Autodesk Fusion 360 part; units mm, degrees
(part 4 of 5)
sketch "cheekR_pa10" plane through (89.6, 0, 0) normal (1, 0, 0) x (0, 0, -1)
  line L0 (18.5, 27) -> (14.8, 27)
  line L1 (14.8, 27) -> (11.1, 27)
  line L2 (11.1, 27) -> (7.4, 27)
  line L3 (7.4, 27) -> (3.7, 27)
  line L4 (3.7, 27) -> (0, 27)
  line L5 (0, 27) -> (-3.7, 27)
  line L6 (-3.7, 27) -> (-7.4, 27)
  line L7 (-7.4, 27) -> (-11.1, 27)
  line L8 (-11.1, 27) -> (-14.8, 27)
  line L9 (-14.8, 27) -> (-18.5, 27)
  line L10 (-18.5, 27) -> (-18.5, 25)
  line L11 (-18.5, 25) -> (-14.8, 25)
  line L12 (-14.8, 25) -> (-11.1, 25)
  line L13 (-11.1, 25) -> (-7.4, 25)
  line L14 (-7.4, 25) -> (-3.7, 25)
  line L15 (-3.7, 25) -> (0, 25)
  line L16 (0, 25) -> (3.7, 25)
  line L17 (3.7, 25) -> (7.4, 25)
  line L18 (7.4, 25) -> (11.1, 25)
  line L19 (11.1, 25) -> (14.8, 25)
  line L20 (14.8, 25) -> (18.5, 25)
  line L21 (18.5, 25) -> (18.5, 27)
ref_plane "WorkPlane94" through (120.4, 0, 0) normal (1, 0, 0) x (0, 1, 0)
sketch "cheekR_pb10" plane through (120.4, 0, 0) normal (1, 0, 0) x (0, 0, -1)
  line L0 (18.5, 27) -> (14.8, 27)
  line L1 (14.8, 27) -> (11.1, 27)
  line L2 (11.1, 27) -> (7.4, 27)
  line L3 (7.4, 27) -> (3.7, 27)
  line L4 (3.7, 27) -> (0, 27)
  line L5 (0, 27) -> (-3.7, 27)
  line L6 (-3.7, 27) -> (-7.4, 27)
  line L7 (-7.4, 27) -> (-11.1, 27)
  line L8 (-11.1, 27) -> (-14.8, 27)
  line L9 (-14.8, 27) -> (-18.5, 27)
  line L10 (-18.5, 27) -> (-18.5, 25)
  line L11 (-18.5, 25) -> (-14.8, 25)
  line L12 (-14.8, 25) -> (-11.1, 25)
  line L13 (-11.1, 25) -> (-7.4, 25)
  line L14 (-7.4, 25) -> (-3.7, 25)
  line L15 (-3.7, 25) -> (0, 25)
  line L16 (0, 25) -> (3.7, 25)
  line L17 (3.7, 25) -> (7.4, 25)
  line L18 (7.4, 25) -> (11.1, 25)
  line L19 (11.1, 25) -> (14.8, 25)
  line L20 (14.8, 25) -> (18.5, 25)
  line L21 (18.5, 25) -> (18.5, 27)
loft "Loft47" add profiles "cheekR_pa10", "cheekR_pb10" section 1 section 2 separate body makes body 47
ref_plane "WorkPlane95" through (119.6, 0, 0) normal (1, 0, 0) x (0, 1, 0)
sketch "cheekR_pa11" plane through (119.6, 0, 0) normal (1, 0, 0) x (0, 0, -1)
  line L0 (18.5, 27) -> (14.8, 27)
  line L1 (14.8, 27) -> (11.1, 27)
  line L2 (11.1, 27) -> (7.4, 27)
  line L3 (7.4, 27) -> (3.7, 27)
  line L4 (3.7, 27) -> (0, 27)
  line L5 (0, 27) -> (-3.7, 27)
  line L6 (-3.7, 27) -> (-7.4, 27)
  line L7 (-7.4, 27) -> (-11.1, 27)
  line L8 (-11.1, 27) -> (-14.8, 27)
  line L9 (-14.8, 27) -> (-18.5, 27)
  line L10 (-18.5, 27) -> (-18.5, 25)
  line L11 (-18.5, 25) -> (-14.8, 25)
  line L12 (-14.8, 25) -> (-11.1, 25)
  line L13 (-11.1, 25) -> (-7.4, 25)
  line L14 (-7.4, 25) -> (-3.7, 25)
  line L15 (-3.7, 25) -> (0, 25)
  line L16 (0, 25) -> (3.7, 25)
  line L17 (3.7, 25) -> (7.4, 25)
  line L18 (7.4, 25) -> (11.1, 25)
  line L19 (11.1, 25) -> (14.8, 25)
  line L20 (14.8, 25) -> (18.5, 25)
  line L21 (18.5, 25) -> (18.5, 27)
ref_plane "WorkPlane96" through (124.6857, 0, 0) normal (1, 0, 0) x (0, 1, 0)
sketch "cheekR_pb11" plane through (124.6857, 0, 0) normal (1, 0, 0) x (0, 0, -1)
  line L0 (16.3003, 24.3221) -> (13.0402, 24.3221)
  line L1 (13.0402, 24.3221) -> (9.7802, 24.3221)
  line L2 (9.7802, 24.3221) -> (6.5201, 24.3221)
  line L3 (6.5201, 24.3221) -> (3.2601, 24.3221)
  line L4 (3.2601, 24.3221) -> (0, 24.3221)
  line L5 (0, 24.3221) -> (-3.2601, 24.3221)
  line L6 (-3.2601, 24.3221) -> (-6.5201, 24.3221)
  line L7 (-6.5201, 24.3221) -> (-9.7802, 24.3221)
  line L8 (-9.7802, 24.3221) -> (-13.0402, 24.3221)
  line L9 (-13.0402, 24.3221) -> (-16.3003, 24.3221)
  line L10 (-16.3003, 24.3221) -> (-16.3003, 22.3221)
  line L11 (-16.3003, 22.3221) -> (-13.0402, 22.3221)
  line L12 (-13.0402, 22.3221) -> (-9.7802, 22.3221)
  line L13 (-9.7802, 22.3221) -> (-6.5201, 22.3221)
  line L14 (-6.5201, 22.3221) -> (-3.2601, 22.3221)
  line L15 (-3.2601, 22.3221) -> (0, 22.3221)
  line L16 (0, 22.3221) -> (3.2601, 22.3221)
  line L17 (3.2601, 22.3221) -> (6.5201, 22.3221)
  line L18 (6.5201, 22.3221) -> (9.7802, 22.3221)
  line L19 (9.7802, 22.3221) -> (13.0402, 22.3221)
  line L20 (13.0402, 22.3221) -> (16.3003, 22.3221)
  line L21 (16.3003, 22.3221) -> (16.3003, 24.3221)
loft "Loft48" add profiles "cheekR_pa11", "cheekR_pb11" section 1 section 2 separate body makes body 48
ref_plane "WorkPlane97" through (123.8857, 0, 0) normal (1, 0, 0) x (0, 1, 0)
sketch "cheekR_pa12" plane through (123.8857, 0, 0) normal (1, 0, 0) x (0, 0, -1)
  line L0 (16.3003, 24.3221) -> (13.0402, 24.3221)
  line L1 (13.0402, 24.3221) -> (9.7802, 24.3221)
  line L2 (9.7802, 24.3221) -> (6.5201, 24.3221)
  line L3 (6.5201, 24.3221) -> (3.2601, 24.3221)
  line L4 (3.2601, 24.3221) -> (0, 24.3221)
  line L5 (0, 24.3221) -> (-3.2601, 24.3221)
  line L6 (-3.2601, 24.3221) -> (-6.5201, 24.3221)
  line L7 (-6.5201, 24.3221) -> (-9.7802, 24.3221)
  line L8 (-9.7802, 24.3221) -> (-13.0402, 24.3221)
  line L9 (-13.0402, 24.3221) -> (-16.3003, 24.3221)
  line L10 (-16.3003, 24.3221) -> (-16.3003, 22.3221)
  line L11 (-16.3003, 22.3221) -> (-13.0402, 22.3221)
  line L12 (-13.0402, 22.3221) -> (-9.7802, 22.3221)
  line L13 (-9.7802, 22.3221) -> (-6.5201, 22.3221)
  line L14 (-6.5201, 22.3221) -> (-3.2601, 22.3221)
  line L15 (-3.2601, 22.3221) -> (0, 22.3221)
  line L16 (0, 22.3221) -> (3.2601, 22.3221)
  line L17 (3.2601, 22.3221) -> (6.5201, 22.3221)
  line L18 (6.5201, 22.3221) -> (9.7802, 22.3221)
  line L19 (9.7802, 22.3221) -> (13.0402, 22.3221)
  line L20 (13.0402, 22.3221) -> (16.3003, 22.3221)
  line L21 (16.3003, 22.3221) -> (16.3003, 24.3221)
ref_plane "WorkPlane98" through (128.9714, 0, 0) normal (1, 0, 0) x (0, 1, 0)
sketch "cheekR_pb12" plane through (128.9714, 0, 0) normal (1, 0, 0) x (0, 0, -1)
  line L0 (14.535, 22.1731) -> (11.628, 22.1731)
  line L1 (11.628, 22.1731) -> (8.721, 22.1731)
  line L2 (8.721, 22.1731) -> (5.814, 22.1731)
  line L3 (5.814, 22.1731) -> (2.907, 22.1731)
  line L4 (2.907, 22.1731) -> (0, 22.1731)
  line L5 (0, 22.1731) -> (-2.907, 22.1731)
  line L6 (-2.907, 22.1731) -> (-5.814, 22.1731)
  line L7 (-5.814, 22.1731) -> (-8.721, 22.1731)
  line L8 (-8.721, 22.1731) -> (-11.628, 22.1731)
  line L9 (-11.628, 22.1731) -> (-14.535, 22.1731)
  line L10 (-14.535, 22.1731) -> (-14.535, 20.1731)
  line L11 (-14.535, 20.1731) -> (-11.628, 20.1731)
  line L12 (-11.628, 20.1731) -> (-8.721, 20.1731)
  line L13 (-8.721, 20.1731) -> (-5.814, 20.1731)
  line L14 (-5.814, 20.1731) -> (-2.907, 20.1731)
  line L15 (-2.907, 20.1731) -> (0, 20.1731)
  line L16 (0, 20.1731) -> (2.907, 20.1731)
  line L17 (2.907, 20.1731) -> (5.814, 20.1731)
  line L18 (5.814, 20.1731) -> (8.721, 20.1731)
  line L19 (8.721, 20.1731) -> (11.628, 20.1731)
  line L20 (11.628, 20.1731) -> (14.535, 20.1731)
  line L21 (14.535, 20.1731) -> (14.535, 22.1731)
loft "Loft49" add profiles "cheekR_pa12", "cheekR_pb12" section 1 section 2 separate body makes body 49
ref_plane "WorkPlane99" through (128.1714, 0, 0) normal (1, 0, 0) x (0, 1, 0)
sketch "cheekR_pa13" plane through (128.1714, 0, 0) normal (1, 0, 0) x (0, 0, -1)
  line L0 (14.535, 22.1731) -> (11.628, 22.1731)
  line L1 (11.628, 22.1731) -> (8.721, 22.1731)
  line L2 (8.721, 22.1731) -> (5.814, 22.1731)
  line L3 (5.814, 22.1731) -> (2.907, 22.1731)
  line L4 (2.907, 22.1731) -> (0, 22.1731)
  line L5 (0, 22.1731) -> (-2.907, 22.1731)
  line L6 (-2.907, 22.1731) -> (-5.814, 22.1731)
  line L7 (-5.814, 22.1731) -> (-8.721, 22.1731)
  line L8 (-8.721, 22.1731) -> (-11.628, 22.1731)
  line L9 (-11.628, 22.1731) -> (-14.535, 22.1731)
  line L10 (-14.535, 22.1731) -> (-14.535, 20.1731)
  line L11 (-14.535, 20.1731) -> (-11.628, 20.1731)
  line L12 (-11.628, 20.1731) -> (-8.721, 20.1731)
  line L13 (-8.721, 20.1731) -> (-5.814, 20.1731)
  line L14 (-5.814, 20.1731) -> (-2.907, 20.1731)
  line L15 (-2.907, 20.1731) -> (0, 20.1731)
  line L16 (0, 20.1731) -> (2.907, 20.1731)
  line L17 (2.907, 20.1731) -> (5.814, 20.1731)
  line L18 (5.814, 20.1731) -> (8.721, 20.1731)
  line L19 (8.721, 20.1731) -> (11.628, 20.1731)
  line L20 (11.628, 20.1731) -> (14.535, 20.1731)
  line L21 (14.535, 20.1731) -> (14.535, 22.1731)
ref_plane "WorkPlane100" through (133.2571, 0, 0) normal (1, 0, 0) x (0, 1, 0)
sketch "cheekR_pb13" plane through (133.2571, 0, 0) normal (1, 0, 0) x (0, 0, -1)
  line L0 (12.9035, 20.1869) -> (10.3228, 20.1869)
  line L1 (10.3228, 20.1869) -> (7.7421, 20.1869)
  line L2 (7.7421, 20.1869) -> (5.1614, 20.1869)
  line L3 (5.1614, 20.1869) -> (2.5807, 20.1869)
  line L4 (2.5807, 20.1869) -> (0, 20.1869)
  line L5 (0, 20.1869) -> (-2.5807, 20.1869)
  line L6 (-2.5807, 20.1869) -> (-5.1614, 20.1869)
  line L7 (-5.1614, 20.1869) -> (-7.7421, 20.1869)
  line L8 (-7.7421, 20.1869) -> (-10.3228, 20.1869)
  line L9 (-10.3228, 20.1869) -> (-12.9035, 20.1869)
  line L10 (-12.9035, 20.1869) -> (-12.9035, 18.1869)
  line L11 (-12.9035, 18.1869) -> (-10.3228, 18.1869)
  line L12 (-10.3228, 18.1869) -> (-7.7421, 18.1869)
  line L13 (-7.7421, 18.1869) -> (-5.1614, 18.1869)
  line L14 (-5.1614, 18.1869) -> (-2.5807, 18.1869)
  line L15 (-2.5807, 18.1869) -> (0, 18.1869)
  line L16 (0, 18.1869) -> (2.5807, 18.1869)
  line L17 (2.5807, 18.1869) -> (5.1614, 18.1869)
  line L18 (5.1614, 18.1869) -> (7.7421, 18.1869)
  line L19 (7.7421, 18.1869) -> (10.3228, 18.1869)
  line L20 (10.3228, 18.1869) -> (12.9035, 18.1869)
  line L21 (12.9035, 18.1869) -> (12.9035, 20.1869)
loft "Loft50" add profiles "cheekR_pa13", "cheekR_pb13" section 1 section 2 separate body makes body 50
ref_plane "WorkPlane101" through (132.4571, 0, 0) normal (1, 0, 0) x (0, 1, 0)
sketch "cheekR_pa14" plane through (132.4571, 0, 0) normal (1, 0, 0) x (0, 0, -1)
  line L0 (12.9035, 20.1869) -> (10.3228, 20.1869)
  line L1 (10.3228, 20.1869) -> (7.7421, 20.1869)
  line L2 (7.7421, 20.1869) -> (5.1614, 20.1869)
  line L3 (5.1614, 20.1869) -> (2.5807, 20.1869)
  line L4 (2.5807, 20.1869) -> (0, 20.1869)
  line L5 (0, 20.1869) -> (-2.5807, 20.1869)
  line L6 (-2.5807, 20.1869) -> (-5.1614, 20.1869)
  line L7 (-5.1614, 20.1869) -> (-7.7421, 20.1869)
  line L8 (-7.7421, 20.1869) -> (-10.3228, 20.1869)
  line L9 (-10.3228, 20.1869) -> (-12.9035, 20.1869)
  line L10 (-12.9035, 20.1869) -> (-12.9035, 18.1869)
  line L11 (-12.9035, 18.1869) -> (-10.3228, 18.1869)
  line L12 (-10.3228, 18.1869) -> (-7.7421, 18.1869)
  line L13 (-7.7421, 18.1869) -> (-5.1614, 18.1869)
  line L14 (-5.1614, 18.1869) -> (-2.5807, 18.1869)
  line L15 (-2.5807, 18.1869) -> (0, 18.1869)
  line L16 (0, 18.1869) -> (2.5807, 18.1869)
  line L17 (2.5807, 18.1869) -> (5.1614, 18.1869)
  line L18 (5.1614, 18.1869) -> (7.7421, 18.1869)
  line L19 (7.7421, 18.1869) -> (10.3228, 18.1869)
  line L20 (10.3228, 18.1869) -> (12.9035, 18.1869)
  line L21 (12.9035, 18.1869) -> (12.9035, 20.1869)
ref_plane "WorkPlane102" through (137.5429, 0, 0) normal (1, 0, 0) x (0, 1, 0)
sketch "cheekR_pb14" plane through (137.5429, 0, 0) normal (1, 0, 0) x (0, 0, -1)
  line L0 (11.3531, 18.2995) -> (9.0825, 18.2995)
  line L1 (9.0825, 18.2995) -> (6.8119, 18.2995)
  line L2 (6.8119, 18.2995) -> (4.5413, 18.2995)
  line L3 (4.5413, 18.2995) -> (2.2706, 18.2995)
  line L4 (2.2706, 18.2995) -> (0, 18.2995)
  line L5 (0, 18.2995) -> (-2.2706, 18.2995)
  line L6 (-2.2706, 18.2995) -> (-4.5413, 18.2995)
  line L7 (-4.5413, 18.2995) -> (-6.8119, 18.2995)
  line L8 (-6.8119, 18.2995) -> (-9.0825, 18.2995)
  line L9 (-9.0825, 18.2995) -> (-11.3531, 18.2995)
  line L10 (-11.3531, 18.2995) -> (-11.3531, 16.2995)
  line L11 (-11.3531, 16.2995) -> (-9.0825, 16.2995)
  line L12 (-9.0825, 16.2995) -> (-6.8119, 16.2995)
  line L13 (-6.8119, 16.2995) -> (-4.5413, 16.2995)
  line L14 (-4.5413, 16.2995) -> (-2.2706, 16.2995)
  line L15 (-2.2706, 16.2995) -> (0, 16.2995)
  line L16 (0, 16.2995) -> (2.2706, 16.2995)
  line L17 (2.2706, 16.2995) -> (4.5413, 16.2995)
  line L18 (4.5413, 16.2995) -> (6.8119, 16.2995)
  line L19 (6.8119, 16.2995) -> (9.0825, 16.2995)
  line L20 (9.0825, 16.2995) -> (11.3531, 16.2995)
  line L21 (11.3531, 16.2995) -> (11.3531, 18.2995)
loft "Loft51" add profiles "cheekR_pa14", "cheekR_pb14" section 1 section 2 separate body makes body 51
ref_plane "WorkPlane103" through (136.7429, 0, 0) normal (1, 0, 0) x (0, 1, 0)
sketch "cheekR_pa15" plane through (136.7429, 0, 0) normal (1, 0, 0) x (0, 0, -1)
  line L0 (11.3531, 18.2995) -> (9.0825, 18.2995)
  line L1 (9.0825, 18.2995) -> (6.8119, 18.2995)
  line L2 (6.8119, 18.2995) -> (4.5413, 18.2995)
  line L3 (4.5413, 18.2995) -> (2.2706, 18.2995)
  line L4 (2.2706, 18.2995) -> (0, 18.2995)
  line L5 (0, 18.2995) -> (-2.2706, 18.2995)
  line L6 (-2.2706, 18.2995) -> (-4.5413, 18.2995)
  line L7 (-4.5413, 18.2995) -> (-6.8119, 18.2995)
  line L8 (-6.8119, 18.2995) -> (-9.0825, 18.2995)
  line L9 (-9.0825, 18.2995) -> (-11.3531, 18.2995)
  line L10 (-11.3531, 18.2995) -> (-11.3531, 16.2995)
  line L11 (-11.3531, 16.2995) -> (-9.0825, 16.2995)
  line L12 (-9.0825, 16.2995) -> (-6.8119, 16.2995)
  line L13 (-6.8119, 16.2995) -> (-4.5413, 16.2995)
  line L14 (-4.5413, 16.2995) -> (-2.2706, 16.2995)
  line L15 (-2.2706, 16.2995) -> (0, 16.2995)
  line L16 (0, 16.2995) -> (2.2706, 16.2995)
  line L17 (2.2706, 16.2995) -> (4.5413, 16.2995)
  line L18 (4.5413, 16.2995) -> (6.8119, 16.2995)
  line L19 (6.8119, 16.2995) -> (9.0825, 16.2995)
  line L20 (9.0825, 16.2995) -> (11.3531, 16.2995)
  line L21 (11.3531, 16.2995) -> (11.3531, 18.2995)
ref_plane "WorkPlane104" through (141.8286, 0, 0) normal (1, 0, 0) x (0, 1, 0)
sketch "cheekR_pb15" plane through (141.8286, 0, 0) normal (1, 0, 0) x (0, 0, -1)
  line L0 (9.8605, 16.4823) -> (7.8884, 16.4823)
  line L1 (7.8884, 16.4823) -> (5.9163, 16.4823)
  line L2 (5.9163, 16.4823) -> (3.9442, 16.4823)
  line L3 (3.9442, 16.4823) -> (1.9721, 16.4823)
  line L4 (1.9721, 16.4823) -> (0, 16.4823)
  line L5 (0, 16.4823) -> (-1.9721, 16.4823)
  line L6 (-1.9721, 16.4823) -> (-3.9442, 16.4823)
  line L7 (-3.9442, 16.4823) -> (-5.9163, 16.4823)
  line L8 (-5.9163, 16.4823) -> (-7.8884, 16.4823)
  line L9 (-7.8884, 16.4823) -> (-9.8605, 16.4823)
  line L10 (-9.8605, 16.4823) -> (-9.8605, 14.4823)
  line L11 (-9.8605, 14.4823) -> (-7.8884, 14.4823)
  line L12 (-7.8884, 14.4823) -> (-5.9163, 14.4823)
  line L13 (-5.9163, 14.4823) -> (-3.9442, 14.4823)
  line L14 (-3.9442, 14.4823) -> (-1.9721, 14.4823)
  line L15 (-1.9721, 14.4823) -> (0, 14.4823)
  line L16 (0, 14.4823) -> (1.9721, 14.4823)
  line L17 (1.9721, 14.4823) -> (3.9442, 14.4823)
  line L18 (3.9442, 14.4823) -> (5.9163, 14.4823)
  line L19 (5.9163, 14.4823) -> (7.8884, 14.4823)
  line L20 (7.8884, 14.4823) -> (9.8605, 14.4823)
  line L21 (9.8605, 14.4823) -> (9.8605, 16.4823)
loft "Loft52" add profiles "cheekR_pa15", "cheekR_pb15" section 1 section 2 separate body makes body 52
ref_plane "WorkPlane105" through (141.0286, 0, 0) normal (1, 0, 0) x (0, 1, 0)
sketch "cheekR_pa16" plane through (141.0286, 0, 0) normal (1, 0, 0) x (0, 0, -1)
  line L0 (9.8605, 16.4823) -> (7.8884, 16.4823)
  line L1 (7.8884, 16.4823) -> (5.9163, 16.4823)
  line L2 (5.9163, 16.4823) -> (3.9442, 16.4823)
  line L3 (3.9442, 16.4823) -> (1.9721, 16.4823)
  line L4 (1.9721, 16.4823) -> (0, 16.4823)
  line L5 (0, 16.4823) -> (-1.9721, 16.4823)
  line L6 (-1.9721, 16.4823) -> (-3.9442, 16.4823)
  line L7 (-3.9442, 16.4823) -> (-5.9163, 16.4823)
  line L8 (-5.9163, 16.4823) -> (-7.8884, 16.4823)
  line L9 (-7.8884, 16.4823) -> (-9.8605, 16.4823)
  line L10 (-9.8605, 16.4823) -> (-9.8605, 14.4823)
  line L11 (-9.8605, 14.4823) -> (-7.8884, 14.4823)
  line L12 (-7.8884, 14.4823) -> (-5.9163, 14.4823)
  line L13 (-5.9163, 14.4823) -> (-3.9442, 14.4823)
  line L14 (-3.9442, 14.4823) -> (-1.9721, 14.4823)
  line L15 (-1.9721, 14.4823) -> (0, 14.4823)
  line L16 (0, 14.4823) -> (1.9721, 14.4823)
  line L17 (1.9721, 14.4823) -> (3.9442, 14.4823)
  line L18 (3.9442, 14.4823) -> (5.9163, 14.4823)
  line L19 (5.9163, 14.4823) -> (7.8884, 14.4823)
  line L20 (7.8884, 14.4823) -> (9.8605, 14.4823)
  line L21 (9.8605, 14.4823) -> (9.8605, 16.4823)
ref_plane "WorkPlane106" through (146.1143, 0, 0) normal (1, 0, 0) x (0, 1, 0)
sketch "cheekR_pb16" plane through (146.1143, 0, 0) normal (1, 0, 0) x (0, 0, -1)
  line L0 (8.4123, 14.7193) -> (6.7298, 14.7193)
  line L1 (6.7298, 14.7193) -> (5.0474, 14.7193)
  line L2 (5.0474, 14.7193) -> (3.3649, 14.7193)
  line L3 (3.3649, 14.7193) -> (1.6825, 14.7193)
  line L4 (1.6825, 14.7193) -> (0, 14.7193)
  line L5 (0, 14.7193) -> (-1.6825, 14.7193)
  line L6 (-1.6825, 14.7193) -> (-3.3649, 14.7193)
  line L7 (-3.3649, 14.7193) -> (-5.0474, 14.7193)
  line L8 (-5.0474, 14.7193) -> (-6.7298, 14.7193)
  line L9 (-6.7298, 14.7193) -> (-8.4123, 14.7193)
  line L10 (-8.4123, 14.7193) -> (-8.4123, 12.7193)
  line L11 (-8.4123, 12.7193) -> (-6.7298, 12.7193)
  line L12 (-6.7298, 12.7193) -> (-5.0474, 12.7193)
  line L13 (-5.0474, 12.7193) -> (-3.3649, 12.7193)
  line L14 (-3.3649, 12.7193) -> (-1.6825, 12.7193)
  line L15 (-1.6825, 12.7193) -> (0, 12.7193)
  line L16 (0, 12.7193) -> (1.6825, 12.7193)
  line L17 (1.6825, 12.7193) -> (3.3649, 12.7193)
  line L18 (3.3649, 12.7193) -> (5.0474, 12.7193)
  line L19 (5.0474, 12.7193) -> (6.7298, 12.7193)
  line L20 (6.7298, 12.7193) -> (8.4123, 12.7193)
  line L21 (8.4123, 12.7193) -> (8.4123, 14.7193)
loft "Loft53" add profiles "cheekR_pa16", "cheekR_pb16" section 1 section 2 separate body makes body 53
ref_plane "WorkPlane107" through (145.3143, 0, 0) normal (1, 0, 0) x (0, 1, 0)
sketch "cheekR_pa17" plane through (145.3143, 0, 0) normal (1, 0, 0) x (0, 0, -1)
  line L0 (8.4123, 14.7193) -> (6.7298, 14.7193)
  line L1 (6.7298, 14.7193) -> (5.0474, 14.7193)
  line L2 (5.0474, 14.7193) -> (3.3649, 14.7193)
  line L3 (3.3649, 14.7193) -> (1.6825, 14.7193)
  line L4 (1.6825, 14.7193) -> (0, 14.7193)
  line L5 (0, 14.7193) -> (-1.6825, 14.7193)
  line L6 (-1.6825, 14.7193) -> (-3.3649, 14.7193)
  line L7 (-3.3649, 14.7193) -> (-5.0474, 14.7193)
  line L8 (-5.0474, 14.7193) -> (-6.7298, 14.7193)
  line L9 (-6.7298, 14.7193) -> (-8.4123, 14.7193)
  line L10 (-8.4123, 14.7193) -> (-8.4123, 12.7193)
  line L11 (-8.4123, 12.7193) -> (-6.7298, 12.7193)
  line L12 (-6.7298, 12.7193) -> (-5.0474, 12.7193)
  line L13 (-5.0474, 12.7193) -> (-3.3649, 12.7193)
  line L14 (-3.3649, 12.7193) -> (-1.6825, 12.7193)
  line L15 (-1.6825, 12.7193) -> (0, 12.7193)
  line L16 (0, 12.7193) -> (1.6825, 12.7193)
  line L17 (1.6825, 12.7193) -> (3.3649, 12.7193)
  line L18 (3.3649, 12.7193) -> (5.0474, 12.7193)
  line L19 (5.0474, 12.7193) -> (6.7298, 12.7193)
  line L20 (6.7298, 12.7193) -> (8.4123, 12.7193)
  line L21 (8.4123, 12.7193) -> (8.4123, 14.7193)
ref_plane "WorkPlane108" through (150, 0, 0) normal (1, 0, 0) x (0, 1, 0)
sketch "cheekR_pb17" plane through (150, 0, 0) normal (1, 0, 0) x (0, 0, -1)
  line L0 (7, 13) -> (5.6, 13)
  line L1 (5.6, 13) -> (4.2, 13)
  line L2 (4.2, 13) -> (2.8, 13)
  line L3 (2.8, 13) -> (1.4, 13)
  line L4 (1.4, 13) -> (0, 13)
  line L5 (0, 13) -> (-1.4, 13)
  line L6 (-1.4, 13) -> (-2.8, 13)
  line L7 (-2.8, 13) -> (-4.2, 13)
  line L8 (-4.2, 13) -> (-5.6, 13)
  line L9 (-5.6, 13) -> (-7, 13)
  line L10 (-7, 13) -> (-7, 11)
  line L11 (-7, 11) -> (-5.6, 11)
  line L12 (-5.6, 11) -> (-4.2, 11)
  line L13 (-4.2, 11) -> (-2.8, 11)
  line L14 (-2.8, 11) -> (-1.4, 11)
  line L15 (-1.4, 11) -> (0, 11)
  line L16 (0, 11) -> (1.4, 11)
  line L17 (1.4, 11) -> (2.8, 11)
  line L18 (2.8, 11) -> (4.2, 11)
  line L19 (4.2, 11) -> (5.6, 11)
  line L20 (5.6, 11) -> (7, 11)
  line L21 (7, 11) -> (7, 13)
loft "Loft54" add profiles "cheekR_pa17", "cheekR_pb17" section 1 section 2 separate body makes body 54
ref_plane "WorkPlane109" through (-24, 0, 0) normal (1, 0, 0) x (0, 1, 0)
sketch "cheekL_pa00" plane through (-24, 0, 0) normal (1, 0, 0) x (0, 0, -1)
  line L0 (22.5, -33) -> (18, -33)
  line L1 (18, -33) -> (13.5, -33)
  line L2 (13.5, -33) -> (9, -33)
  line L3 (9, -33) -> (4.5, -33)
  line L4 (4.5, -33) -> (0, -33)
  line L5 (0, -33) -> (-4.5, -33)
  line L6 (-4.5, -33) -> (-9, -33)
  line L7 (-9, -33) -> (-13.5, -33)
  line L8 (-13.5, -33) -> (-18, -33)
  line L9 (-18, -33) -> (-22.5, -33)
  line L10 (-22.5, -33) -> (-22.5, -31)
  line L11 (-22.5, -31) -> (-18, -31)
  line L12 (-18, -31) -> (-13.5, -31)
  line L13 (-13.5, -31) -> (-9, -31)
  line L14 (-9, -31) -> (-4.5, -31)
  line L15 (-4.5, -31) -> (0, -31)
  line L16 (0, -31) -> (4.5, -31)
  line L17 (4.5, -31) -> (9, -31)
  line L18 (9, -31) -> (13.5, -31)
  line L19 (13.5, -31) -> (18, -31)
  line L20 (18, -31) -> (22.5, -31)
  line L21 (22.5, -31) -> (22.5, -33)
ref_plane "WorkPlane110" through (-20.1714, 0, 0) normal (1, 0, 0) x (0, 1, 0)
sketch "cheekL_pb00" plane through (-20.1714, 0, 0) normal (1, 0, 0) x (0, 0, -1)
  line L0 (22.3997, -32.8496) -> (17.9198, -32.8496)
  line L1 (17.9198, -32.8496) -> (13.4398, -32.8496)
  line L2 (13.4398, -32.8496) -> (8.9599, -32.8496)
  line L3 (8.9599, -32.8496) -> (4.4799, -32.8496)
  line L4 (4.4799, -32.8496) -> (0, -32.8496)
  line L5 (0, -32.8496) -> (-4.4799, -32.8496)
  line L6 (-4.4799, -32.8496) -> (-8.9599, -32.8496)
  line L7 (-8.9599, -32.8496) -> (-13.4398, -32.8496)
  line L8 (-13.4398, -32.8496) -> (-17.9198, -32.8496)
  line L9 (-17.9198, -32.8496) -> (-22.3997, -32.8496)
  line L10 (-22.3997, -32.8496) -> (-22.3997, -30.8496)
  line L11 (-22.3997, -30.8496) -> (-17.9198, -30.8496)
  line L12 (-17.9198, -30.8496) -> (-13.4398, -30.8496)
  line L13 (-13.4398, -30.8496) -> (-8.9599, -30.8496)
  line L14 (-8.9599, -30.8496) -> (-4.4799, -30.8496)
  line L15 (-4.4799, -30.8496) -> (0, -30.8496)
  line L16 (0, -30.8496) -> (4.4799, -30.8496)
  line L17 (4.4799, -30.8496) -> (8.9599, -30.8496)
  line L18 (8.9599, -30.8496) -> (13.4398, -30.8496)
  line L19 (13.4398, -30.8496) -> (17.9198, -30.8496)
  line L20 (17.9198, -30.8496) -> (22.3997, -30.8496)
  line L21 (22.3997, -30.8496) -> (22.3997, -32.8496)
loft "Loft55" add profiles "cheekL_pa00", "cheekL_pb00" section 1 section 2 separate body makes body 55
ref_plane "WorkPlane111" through (-20.9714, 0, 0) normal (1, 0, 0) x (0, 1, 0)
sketch "cheekL_pa01" plane through (-20.9714, 0, 0) normal (1, 0, 0) x (0, 0, -1)
  line L0 (22.3997, -32.8496) -> (17.9198, -32.8496)
  line L1 (17.9198, -32.8496) -> (13.4398, -32.8496)
  line L2 (13.4398, -32.8496) -> (8.9599, -32.8496)
  line L3 (8.9599, -32.8496) -> (4.4799, -32.8496)
  line L4 (4.4799, -32.8496) -> (0, -32.8496)
  line L5 (0, -32.8496) -> (-4.4799, -32.8496)
  line L6 (-4.4799, -32.8496) -> (-8.9599, -32.8496)
  line L7 (-8.9599, -32.8496) -> (-13.4398, -32.8496)
  line L8 (-13.4398, -32.8496) -> (-17.9198, -32.8496)
  line L9 (-17.9198, -32.8496) -> (-22.3997, -32.8496)
  line L10 (-22.3997, -32.8496) -> (-22.3997, -30.8496)
  line L11 (-22.3997, -30.8496) -> (-17.9198, -30.8496)
  line L12 (-17.9198, -30.8496) -> (-13.4398, -30.8496)
  line L13 (-13.4398, -30.8496) -> (-8.9599, -30.8496)
  line L14 (-8.9599, -30.8496) -> (-4.4799, -30.8496)
  line L15 (-4.4799, -30.8496) -> (0, -30.8496)
  line L16 (0, -30.8496) -> (4.4799, -30.8496)
  line L17 (4.4799, -30.8496) -> (8.9599, -30.8496)
  line L18 (8.9599, -30.8496) -> (13.4398, -30.8496)
  line L19 (13.4398, -30.8496) -> (17.9198, -30.8496)
  line L20 (17.9198, -30.8496) -> (22.3997, -30.8496)
  line L21 (22.3997, -30.8496) -> (22.3997, -32.8496)
ref_plane "WorkPlane112" through (-16.7429, 0, 0) normal (1, 0, 0) x (0, 1, 0)
sketch "cheekL_pb01" plane through (-16.7429, 0, 0) normal (1, 0, 0) x (0, 0, -1)
  line L0 (22.1039, -32.4058) -> (17.6831, -32.4058)
  line L1 (17.6831, -32.4058) -> (13.2623, -32.4058)
  line L2 (13.2623, -32.4058) -> (8.8416, -32.4058)
  line L3 (8.8416, -32.4058) -> (4.4208, -32.4058)
  line L4 (4.4208, -32.4058) -> (0, -32.4058)
  line L5 (0, -32.4058) -> (-4.4208, -32.4058)
  line L6 (-4.4208, -32.4058) -> (-8.8416, -32.4058)
  line L7 (-8.8416, -32.4058) -> (-13.2623, -32.4058)
  line L8 (-13.2623, -32.4058) -> (-17.6831, -32.4058)
  line L9 (-17.6831, -32.4058) -> (-22.1039, -32.4058)
  line L10 (-22.1039, -32.4058) -> (-22.1039, -30.4058)
  line L11 (-22.1039, -30.4058) -> (-17.6831, -30.4058)
  line L12 (-17.6831, -30.4058) -> (-13.2623, -30.4058)
  line L13 (-13.2623, -30.4058) -> (-8.8416, -30.4058)
  line L14 (-8.8416, -30.4058) -> (-4.4208, -30.4058)
  line L15 (-4.4208, -30.4058) -> (0, -30.4058)
  line L16 (0, -30.4058) -> (4.4208, -30.4058)
  line L17 (4.4208, -30.4058) -> (8.8416, -30.4058)
  line L18 (8.8416, -30.4058) -> (13.2623, -30.4058)
  line L19 (13.2623, -30.4058) -> (17.6831, -30.4058)
  line L20 (17.6831, -30.4058) -> (22.1039, -30.4058)
  line L21 (22.1039, -30.4058) -> (22.1039, -32.4058)
loft "Loft56" add profiles "cheekL_pa01", "cheekL_pb01" section 1 section 2 separate body makes body 56
ref_plane "WorkPlane113" through (-17.5429, 0, 0) normal (1, 0, 0) x (0, 1, 0)
sketch "cheekL_pa02" plane through (-17.5429, 0, 0) normal (1, 0, 0) x (0, 0, -1)
  line L0 (22.1039, -32.4058) -> (17.6831, -32.4058)
  line L1 (17.6831, -32.4058) -> (13.2623, -32.4058)
  line L2 (13.2623, -32.4058) -> (8.8416, -32.4058)
  line L3 (8.8416, -32.4058) -> (4.4208, -32.4058)
  line L4 (4.4208, -32.4058) -> (0, -32.4058)
  line L5 (0, -32.4058) -> (-4.4208, -32.4058)
  line L6 (-4.4208, -32.4058) -> (-8.8416, -32.4058)
  line L7 (-8.8416, -32.4058) -> (-13.2623, -32.4058)
  line L8 (-13.2623, -32.4058) -> (-17.6831, -32.4058)
  line L9 (-17.6831, -32.4058) -> (-22.1039, -32.4058)
  line L10 (-22.1039, -32.4058) -> (-22.1039, -30.4058)
  line L11 (-22.1039, -30.4058) -> (-17.6831, -30.4058)
  line L12 (-17.6831, -30.4058) -> (-13.2623, -30.4058)
  line L13 (-13.2623, -30.4058) -> (-8.8416, -30.4058)
  line L14 (-8.8416, -30.4058) -> (-4.4208, -30.4058)
  line L15 (-4.4208, -30.4058) -> (0, -30.4058)
  line L16 (0, -30.4058) -> (4.4208, -30.4058)
  line L17 (4.4208, -30.4058) -> (8.8416, -30.4058)
  line L18 (8.8416, -30.4058) -> (13.2623, -30.4058)
  line L19 (13.2623, -30.4058) -> (17.6831, -30.4058)
  line L20 (17.6831, -30.4058) -> (22.1039, -30.4058)
  line L21 (22.1039, -30.4058) -> (22.1039, -32.4058)
ref_plane "WorkPlane114" through (-13.3143, 0, 0) normal (1, 0, 0) x (0, 1, 0)
sketch "cheekL_pb02" plane through (-13.3143, 0, 0) normal (1, 0, 0) x (0, 0, -1)
  line L0 (21.6273, -31.691) -> (17.3019, -31.691)
  line L1 (17.3019, -31.691) -> (12.9764, -31.691)
  line L2 (12.9764, -31.691) -> (8.6509, -31.691)
  line L3 (8.6509, -31.691) -> (4.3255, -31.691)
  line L4 (4.3255, -31.691) -> (0, -31.691)
  line L5 (0, -31.691) -> (-4.3255, -31.691)
  line L6 (-4.3255, -31.691) -> (-8.6509, -31.691)
  line L7 (-8.6509, -31.691) -> (-12.9764, -31.691)
  line L8 (-12.9764, -31.691) -> (-17.3019, -31.691)
  line L9 (-17.3019, -31.691) -> (-21.6273, -31.691)
  line L10 (-21.6273, -31.691) -> (-21.6273, -29.691)
  line L11 (-21.6273, -29.691) -> (-17.3019, -29.691)
  line L12 (-17.3019, -29.691) -> (-12.9764, -29.691)
  line L13 (-12.9764, -29.691) -> (-8.6509, -29.691)
  line L14 (-8.6509, -29.691) -> (-4.3255, -29.691)
  line L15 (-4.3255, -29.691) -> (0, -29.691)
  line L16 (0, -29.691) -> (4.3255, -29.691)
  line L17 (4.3255, -29.691) -> (8.6509, -29.691)
  line L18 (8.6509, -29.691) -> (12.9764, -29.691)
  line L19 (12.9764, -29.691) -> (17.3019, -29.691)
  line L20 (17.3019, -29.691) -> (21.6273, -29.691)
  line L21 (21.6273, -29.691) -> (21.6273, -31.691)
loft "Loft57" add profiles "cheekL_pa02", "cheekL_pb02" section 1 section 2 separate body makes body 57
ref_plane "WorkPlane115" through (-14.1143, 0, 0) normal (1, 0, 0) x (0, 1, 0)
sketch "cheekL_pa03" plane through (-14.1143, 0, 0) normal (1, 0, 0) x (0, 0, -1)
  line L0 (21.6273, -31.691) -> (17.3019, -31.691)
  line L1 (17.3019, -31.691) -> (12.9764, -31.691)
  line L2 (12.9764, -31.691) -> (8.6509, -31.691)
  line L3 (8.6509, -31.691) -> (4.3255, -31.691)
  line L4 (4.3255, -31.691) -> (0, -31.691)
  line L5 (0, -31.691) -> (-4.3255, -31.691)
  line L6 (-4.3255, -31.691) -> (-8.6509, -31.691)
  line L7 (-8.6509, -31.691) -> (-12.9764, -31.691)
  line L8 (-12.9764, -31.691) -> (-17.3019, -31.691)
  line L9 (-17.3019, -31.691) -> (-21.6273, -31.691)
  line L10 (-21.6273, -31.691) -> (-21.6273, -29.691)
  line L11 (-21.6273, -29.691) -> (-17.3019, -29.691)
  line L12 (-17.3019, -29.691) -> (-12.9764, -29.691)
  line L13 (-12.9764, -29.691) -> (-8.6509, -29.691)
  line L14 (-8.6509, -29.691) -> (-4.3255, -29.691)
  line L15 (-4.3255, -29.691) -> (0, -29.691)
  line L16 (0, -29.691) -> (4.3255, -29.691)
  line L17 (4.3255, -29.691) -> (8.6509, -29.691)
  line L18 (8.6509, -29.691) -> (12.9764, -29.691)
  line L19 (12.9764, -29.691) -> (17.3019, -29.691)
  line L20 (17.3019, -29.691) -> (21.6273, -29.691)
  line L21 (21.6273, -29.691) -> (21.6273, -31.691)
ref_plane "WorkPlane116" through (-9.8857, 0, 0) normal (1, 0, 0) x (0, 1, 0)
sketch "cheekL_pb03" plane through (-9.8857, 0, 0) normal (1, 0, 0) x (0, 0, -1)
  line L0 (20.994, -30.7409) -> (16.7952, -30.7409)
  line L1 (16.7952, -30.7409) -> (12.5964, -30.7409)
  line L2 (12.5964, -30.7409) -> (8.3976, -30.7409)
  line L3 (8.3976, -30.7409) -> (4.1988, -30.7409)
  line L4 (4.1988, -30.7409) -> (0, -30.7409)
  line L5 (0, -30.7409) -> (-4.1988, -30.7409)
  line L6 (-4.1988, -30.7409) -> (-8.3976, -30.7409)
  line L7 (-8.3976, -30.7409) -> (-12.5964, -30.7409)
  line L8 (-12.5964, -30.7409) -> (-16.7952, -30.7409)
  line L9 (-16.7952, -30.7409) -> (-20.994, -30.7409)
  line L10 (-20.994, -30.7409) -> (-20.994, -28.7409)
  line L11 (-20.994, -28.7409) -> (-16.7952, -28.7409)
  line L12 (-16.7952, -28.7409) -> (-12.5964, -28.7409)
  line L13 (-12.5964, -28.7409) -> (-8.3976, -28.7409)
  line L14 (-8.3976, -28.7409) -> (-4.1988, -28.7409)
  line L15 (-4.1988, -28.7409) -> (0, -28.7409)
  line L16 (0, -28.7409) -> (4.1988, -28.7409)
  line L17 (4.1988, -28.7409) -> (8.3976, -28.7409)
  line L18 (8.3976, -28.7409) -> (12.5964, -28.7409)
  line L19 (12.5964, -28.7409) -> (16.7952, -28.7409)
  line L20 (16.7952, -28.7409) -> (20.994, -28.7409)
  line L21 (20.994, -28.7409) -> (20.994, -30.7409)
loft "Loft58" add profiles "cheekL_pa03", "cheekL_pb03" section 1 section 2 separate body makes body 58
ref_plane "WorkPlane117" through (-10.6857, 0, 0) normal (1, 0, 0) x (0, 1, 0)
sketch "cheekL_pa04" plane through (-10.6857, 0, 0) normal (1, 0, 0) x (0, 0, -1)
  line L0 (20.994, -30.7409) -> (16.7952, -30.7409)
  line L1 (16.7952, -30.7409) -> (12.5964, -30.7409)
  line L2 (12.5964, -30.7409) -> (8.3976, -30.7409)
  line L3 (8.3976, -30.7409) -> (4.1988, -30.7409)
  line L4 (4.1988, -30.7409) -> (0, -30.7409)
  line L5 (0, -30.7409) -> (-4.1988, -30.7409)
  line L6 (-4.1988, -30.7409) -> (-8.3976, -30.7409)
  line L7 (-8.3976, -30.7409) -> (-12.5964, -30.7409)
  line L8 (-12.5964, -30.7409) -> (-16.7952, -30.7409)
  line L9 (-16.7952, -30.7409) -> (-20.994, -30.7409)
  line L10 (-20.994, -30.7409) -> (-20.994, -28.7409)
  line L11 (-20.994, -28.7409) -> (-16.7952, -28.7409)
  line L12 (-16.7952, -28.7409) -> (-12.5964, -28.7409)
  line L13 (-12.5964, -28.7409) -> (-8.3976, -28.7409)
  line L14 (-8.3976, -28.7409) -> (-4.1988, -28.7409)
  line L15 (-4.1988, -28.7409) -> (0, -28.7409)
  line L16 (0, -28.7409) -> (4.1988, -28.7409)
  line L17 (4.1988, -28.7409) -> (8.3976, -28.7409)
  line L18 (8.3976, -28.7409) -> (12.5964, -28.7409)
  line L19 (12.5964, -28.7409) -> (16.7952, -28.7409)
  line L20 (16.7952, -28.7409) -> (20.994, -28.7409)
  line L21 (20.994, -28.7409) -> (20.994, -30.7409)
ref_plane "WorkPlane118" through (-6.4571, 0, 0) normal (1, 0, 0) x (0, 1, 0)
sketch "cheekL_pb04" plane through (-6.4571, 0, 0) normal (1, 0, 0) x (0, 0, -1)
  line L0 (20.2355, -29.6033) -> (16.1884, -29.6033)
  line L1 (16.1884, -29.6033) -> (12.1413, -29.6033)
  line L2 (12.1413, -29.6033) -> (8.0942, -29.6033)
  line L3 (8.0942, -29.6033) -> (4.0471, -29.6033)
  line L4 (4.0471, -29.6033) -> (0, -29.6033)
  line L5 (0, -29.6033) -> (-4.0471, -29.6033)
  line L6 (-4.0471, -29.6033) -> (-8.0942, -29.6033)
  line L7 (-8.0942, -29.6033) -> (-12.1413, -29.6033)
  line L8 (-12.1413, -29.6033) -> (-16.1884, -29.6033)
  line L9 (-16.1884, -29.6033) -> (-20.2355, -29.6033)
  line L10 (-20.2355, -29.6033) -> (-20.2355, -27.6033)
  line L11 (-20.2355, -27.6033) -> (-16.1884, -27.6033)
  line L12 (-16.1884, -27.6033) -> (-12.1413, -27.6033)
  line L13 (-12.1413, -27.6033) -> (-8.0942, -27.6033)
  line L14 (-8.0942, -27.6033) -> (-4.0471, -27.6033)
  line L15 (-4.0471, -27.6033) -> (0, -27.6033)
  line L16 (0, -27.6033) -> (4.0471, -27.6033)
  line L17 (4.0471, -27.6033) -> (8.0942, -27.6033)
  line L18 (8.0942, -27.6033) -> (12.1413, -27.6033)
  line L19 (12.1413, -27.6033) -> (16.1884, -27.6033)
  line L20 (16.1884, -27.6033) -> (20.2355, -27.6033)
  line L21 (20.2355, -27.6033) -> (20.2355, -29.6033)
loft "Loft59" add profiles "cheekL_pa04", "cheekL_pb04" section 1 section 2 separate body makes body 59
ref_plane "WorkPlane119" through (-7.2571, 0, 0) normal (1, 0, 0) x (0, 1, 0)
sketch "cheekL_pa05" plane through (-7.2571, 0, 0) normal (1, 0, 0) x (0, 0, -1)
  line L0 (20.2355, -29.6033) -> (16.1884, -29.6033)
  line L1 (16.1884, -29.6033) -> (12.1413, -29.6033)
  line L2 (12.1413, -29.6033) -> (8.0942, -29.6033)
  line L3 (8.0942, -29.6033) -> (4.0471, -29.6033)
  line L4 (4.0471, -29.6033) -> (0, -29.6033)
  line L5 (0, -29.6033) -> (-4.0471, -29.6033)
  line L6 (-4.0471, -29.6033) -> (-8.0942, -29.6033)
  line L7 (-8.0942, -29.6033) -> (-12.1413, -29.6033)
  line L8 (-12.1413, -29.6033) -> (-16.1884, -29.6033)
  line L9 (-16.1884, -29.6033) -> (-20.2355, -29.6033)
  line L10 (-20.2355, -29.6033) -> (-20.2355, -27.6033)
  line L11 (-20.2355, -27.6033) -> (-16.1884, -27.6033)
  line L12 (-16.1884, -27.6033) -> (-12.1413, -27.6033)
  line L13 (-12.1413, -27.6033) -> (-8.0942, -27.6033)
  line L14 (-8.0942, -27.6033) -> (-4.0471, -27.6033)
  line L15 (-4.0471, -27.6033) -> (0, -27.6033)
  line L16 (0, -27.6033) -> (4.0471, -27.6033)
  line L17 (4.0471, -27.6033) -> (8.0942, -27.6033)
  line L18 (8.0942, -27.6033) -> (12.1413, -27.6033)
  line L19 (12.1413, -27.6033) -> (16.1884, -27.6033)
  line L20 (16.1884, -27.6033) -> (20.2355, -27.6033)
  line L21 (20.2355, -27.6033) -> (20.2355, -29.6033)
ref_plane "WorkPlane120" through (-3.0286, 0, 0) normal (1, 0, 0) x (0, 1, 0)
sketch "cheekL_pb05" plane through (-3.0286, 0, 0) normal (1, 0, 0) x (0, 0, -1)
  line L0 (19.3901, -28.3351) -> (15.5121, -28.3351)
  line L1 (15.5121, -28.3351) -> (11.6341, -28.3351)
  line L2 (11.6341, -28.3351) -> (7.756, -28.3351)
  line L3 (7.756, -28.3351) -> (3.878, -28.3351)
  line L4 (3.878, -28.3351) -> (0, -28.3351)
  line L5 (0, -28.3351) -> (-3.878, -28.3351)
  line L6 (-3.878, -28.3351) -> (-7.756, -28.3351)
  line L7 (-7.756, -28.3351) -> (-11.6341, -28.3351)
  line L8 (-11.6341, -28.3351) -> (-15.5121, -28.3351)
  line L9 (-15.5121, -28.3351) -> (-19.3901, -28.3351)
  line L10 (-19.3901, -28.3351) -> (-19.3901, -26.3351)
  line L11 (-19.3901, -26.3351) -> (-15.5121, -26.3351)
  line L12 (-15.5121, -26.3351) -> (-11.6341, -26.3351)
  line L13 (-11.6341, -26.3351) -> (-7.756, -26.3351)
  line L14 (-7.756, -26.3351) -> (-3.878, -26.3351)
  line L15 (-3.878, -26.3351) -> (0, -26.3351)
  line L16 (0, -26.3351) -> (3.878, -26.3351)
  line L17 (3.878, -26.3351) -> (7.756, -26.3351)
  line L18 (7.756, -26.3351) -> (11.6341, -26.3351)
  line L19 (11.6341, -26.3351) -> (15.5121, -26.3351)
  line L20 (15.5121, -26.3351) -> (19.3901, -26.3351)
  line L21 (19.3901, -26.3351) -> (19.3901, -28.3351)
loft "Loft60" add profiles "cheekL_pa05", "cheekL_pb05" section 1 section 2 separate body makes body 60
ref_plane "WorkPlane121" through (-3.8286, 0, 0) normal (1, 0, 0) x (0, 1, 0)
sketch "cheekL_pa06" plane through (-3.8286, 0, 0) normal (1, 0, 0) x (0, 0, -1)
  line L0 (19.3901, -28.3351) -> (15.5121, -28.3351)
  line L1 (15.5121, -28.3351) -> (11.6341, -28.3351)
  line L2 (11.6341, -28.3351) -> (7.756, -28.3351)
  line L3 (7.756, -28.3351) -> (3.878, -28.3351)
  line L4 (3.878, -28.3351) -> (0, -28.3351)
  line L5 (0, -28.3351) -> (-3.878, -28.3351)
  line L6 (-3.878, -28.3351) -> (-7.756, -28.3351)
  line L7 (-7.756, -28.3351) -> (-11.6341, -28.3351)
  line L8 (-11.6341, -28.3351) -> (-15.5121, -28.3351)
  line L9 (-15.5121, -28.3351) -> (-19.3901, -28.3351)
  line L10 (-19.3901, -28.3351) -> (-19.3901, -26.3351)
  line L11 (-19.3901, -26.3351) -> (-15.5121, -26.3351)
  line L12 (-15.5121, -26.3351) -> (-11.6341, -26.3351)
  line L13 (-11.6341, -26.3351) -> (-7.756, -26.3351)
  line L14 (-7.756, -26.3351) -> (-3.878, -26.3351)
  line L15 (-3.878, -26.3351) -> (0, -26.3351)
  line L16 (0, -26.3351) -> (3.878, -26.3351)
  line L17 (3.878, -26.3351) -> (7.756, -26.3351)
  line L18 (7.756, -26.3351) -> (11.6341, -26.3351)
  line L19 (11.6341, -26.3351) -> (15.5121, -26.3351)
  line L20 (15.5121, -26.3351) -> (19.3901, -26.3351)
  line L21 (19.3901, -26.3351) -> (19.3901, -28.3351)
ref_plane "WorkPlane122" through (0.4, 0, 0) normal (1, 0, 0) x (0, 1, 0)
sketch "cheekL_pb06" plane through (0.4, 0, 0) normal (1, 0, 0) x (0, 0, -1)
  line L0 (18.5, -27) -> (14.8, -27)
  line L1 (14.8, -27) -> (11.1, -27)
  line L2 (11.1, -27) -> (7.4, -27)
  line L3 (7.4, -27) -> (3.7, -27)
  line L4 (3.7, -27) -> (0, -27)
  line L5 (0, -27) -> (-3.7, -27)
  line L6 (-3.7, -27) -> (-7.4, -27)
  line L7 (-7.4, -27) -> (-11.1, -27)
  line L8 (-11.1, -27) -> (-14.8, -27)
  line L9 (-14.8, -27) -> (-18.5, -27)
  line L10 (-18.5, -27) -> (-18.5, -25)
  line L11 (-18.5, -25) -> (-14.8, -25)
  line L12 (-14.8, -25) -> (-11.1, -25)
  line L13 (-11.1, -25) -> (-7.4, -25)
  line L14 (-7.4, -25) -> (-3.7, -25)
  line L15 (-3.7, -25) -> (0, -25)
  line L16 (0, -25) -> (3.7, -25)
  line L17 (3.7, -25) -> (7.4, -25)
  line L18 (7.4, -25) -> (11.1, -25)
  line L19 (11.1, -25) -> (14.8, -25)
  line L20 (14.8, -25) -> (18.5, -25)
  line L21 (18.5, -25) -> (18.5, -27)
loft "Loft61" add profiles "cheekL_pa06", "cheekL_pb06" section 1 section 2 separate body makes body 61
ref_plane "WorkPlane123" through (-0.4, 0, 0) normal (1, 0, 0) x (0, 1, 0)
sketch "cheekL_pa07" plane through (-0.4, 0, 0) normal (1, 0, 0) x (0, 0, -1)
  line L0 (18.5, -27) -> (14.8, -27)
  line L1 (14.8, -27) -> (11.1, -27)
  line L2 (11.1, -27) -> (7.4, -27)
  line L3 (7.4, -27) -> (3.7, -27)
  line L4 (3.7, -27) -> (0, -27)
  line L5 (0, -27) -> (-3.7, -27)
  line L6 (-3.7, -27) -> (-7.4, -27)
  line L7 (-7.4, -27) -> (-11.1, -27)
  line L8 (-11.1, -27) -> (-14.8, -27)
  line L9 (-14.8, -27) -> (-18.5, -27)
  line L10 (-18.5, -27) -> (-18.5, -25)
  line L11 (-18.5, -25) -> (-14.8, -25)
  line L12 (-14.8, -25) -> (-11.1, -25)
  line L13 (-11.1, -25) -> (-7.4, -25)
  line L14 (-7.4, -25) -> (-3.7, -25)
  line L15 (-3.7, -25) -> (0, -25)
  line L16 (0, -25) -> (3.7, -25)
  line L17 (3.7, -25) -> (7.4, -25)
  line L18 (7.4, -25) -> (11.1, -25)
  line L19 (11.1, -25) -> (14.8, -25)
  line L20 (14.8, -25) -> (18.5, -25)
  line L21 (18.5, -25) -> (18.5, -27)
ref_plane "WorkPlane124" through (30.4, 0, 0) normal (1, 0, 0) x (0, 1, 0)
sketch "cheekL_pb07" plane through (30.4, 0, 0) normal (1, 0, 0) x (0, 0, -1)
  line L0 (18.5, -27) -> (14.8, -27)
  line L1 (14.8, -27) -> (11.1, -27)
  line L2 (11.1, -27) -> (7.4, -27)
  line L3 (7.4, -27) -> (3.7, -27)
  line L4 (3.7, -27) -> (0, -27)
  line L5 (0, -27) -> (-3.7, -27)
  line L6 (-3.7, -27) -> (-7.4, -27)
  line L7 (-7.4, -27) -> (-11.1, -27)
  line L8 (-11.1, -27) -> (-14.8, -27)
  line L9 (-14.8, -27) -> (-18.5, -27)
  line L10 (-18.5, -27) -> (-18.5, -25)
  line L11 (-18.5, -25) -> (-14.8, -25)
  line L12 (-14.8, -25) -> (-11.1, -25)
  line L13 (-11.1, -25) -> (-7.4, -25)
  line L14 (-7.4, -25) -> (-3.7, -25)
  line L15 (-3.7, -25) -> (0, -25)
  line L16 (0, -25) -> (3.7, -25)
  line L17 (3.7, -25) -> (7.4, -25)
  line L18 (7.4, -25) -> (11.1, -25)
  line L19 (11.1, -25) -> (14.8, -25)
  line L20 (14.8, -25) -> (18.5, -25)
  line L21 (18.5, -25) -> (18.5, -27)
loft "Loft62" add profiles "cheekL_pa07", "cheekL_pb07" section 1 section 2 separate body makes body 62
ref_plane "WorkPlane125" through (29.6, 0, 0) normal (1, 0, 0) x (0, 1, 0)
sketch "cheekL_pa08" plane through (29.6, 0, 0) normal (1, 0, 0) x (0, 0, -1)
  line L0 (18.5, -27) -> (14.8, -27)
  line L1 (14.8, -27) -> (11.1, -27)
  line L2 (11.1, -27) -> (7.4, -27)
  line L3 (7.4, -27) -> (3.7, -27)
  line L4 (3.7, -27) -> (0, -27)
  line L5 (0, -27) -> (-3.7, -27)
  line L6 (-3.7, -27) -> (-7.4, -27)
  line L7 (-7.4, -27) -> (-11.1, -27)
  line L8 (-11.1, -27) -> (-14.8, -27)
  line L9 (-14.8, -27) -> (-18.5, -27)
  line L10 (-18.5, -27) -> (-18.5, -25)
  line L11 (-18.5, -25) -> (-14.8, -25)
  line L12 (-14.8, -25) -> (-11.1, -25)
  line L13 (-11.1, -25) -> (-7.4, -25)
  line L14 (-7.4, -25) -> (-3.7, -25)
  line L15 (-3.7, -25) -> (0, -25)
  line L16 (0, -25) -> (3.7, -25)
  line L17 (3.7, -25) -> (7.4, -25)
  line L18 (7.4, -25) -> (11.1, -25)
  line L19 (11.1, -25) -> (14.8, -25)
  line L20 (14.8, -25) -> (18.5, -25)
  line L21 (18.5, -25) -> (18.5, -27)
ref_plane "WorkPlane126" through (60.4, 0, 0) normal (1, 0, 0) x (0, 1, 0)
sketch "cheekL_pb08" plane through (60.4, 0, 0) normal (1, 0, 0) x (0, 0, -1)
  line L0 (18.5, -27) -> (14.8, -27)
  line L1 (14.8, -27) -> (11.1, -27)
  line L2 (11.1, -27) -> (7.4, -27)
  line L3 (7.4, -27) -> (3.7, -27)
  line L4 (3.7, -27) -> (0, -27)
  line L5 (0, -27) -> (-3.7, -27)
  line L6 (-3.7, -27) -> (-7.4, -27)
  line L7 (-7.4, -27) -> (-11.1, -27)
  line L8 (-11.1, -27) -> (-14.8, -27)
  line L9 (-14.8, -27) -> (-18.5, -27)
  line L10 (-18.5, -27) -> (-18.5, -25)
  line L11 (-18.5, -25) -> (-14.8, -25)
  line L12 (-14.8, -25) -> (-11.1, -25)
  line L13 (-11.1, -25) -> (-7.4, -25)
  line L14 (-7.4, -25) -> (-3.7, -25)
  line L15 (-3.7, -25) -> (0, -25)
  line L16 (0, -25) -> (3.7, -25)
  line L17 (3.7, -25) -> (7.4, -25)
  line L18 (7.4, -25) -> (11.1, -25)
  line L19 (11.1, -25) -> (14.8, -25)
  line L20 (14.8, -25) -> (18.5, -25)
  line L21 (18.5, -25) -> (18.5, -27)
loft "Loft63" add profiles "cheekL_pa08", "cheekL_pb08" section 1 section 2 separate body makes body 63
ref_plane "WorkPlane127" through (59.6, 0, 0) normal (1, 0, 0) x (0, 1, 0)
sketch "cheekL_pa09" plane through (59.6, 0, 0) normal (1, 0, 0) x (0, 0, -1)
  line L0 (18.5, -27) -> (14.8, -27)
  line L1 (14.8, -27) -> (11.1, -27)
  line L2 (11.1, -27) -> (7.4, -27)
  line L3 (7.4, -27) -> (3.7, -27)
  line L4 (3.7, -27) -> (0, -27)
  line L5 (0, -27) -> (-3.7, -27)
  line L6 (-3.7, -27) -> (-7.4, -27)
  line L7 (-7.4, -27) -> (-11.1, -27)
  line L8 (-11.1, -27) -> (-14.8, -27)
  line L9 (-14.8, -27) -> (-18.5, -27)
  line L10 (-18.5, -27) -> (-18.5, -25)
  line L11 (-18.5, -25) -> (-14.8, -25)
  line L12 (-14.8, -25) -> (-11.1, -25)
  line L13 (-11.1, -25) -> (-7.4, -25)
  line L14 (-7.4, -25) -> (-3.7, -25)
  line L15 (-3.7, -25) -> (0, -25)
  line L16 (0, -25) -> (3.7, -25)
  line L17 (3.7, -25) -> (7.4, -25)
  line L18 (7.4, -25) -> (11.1, -25)
  line L19 (11.1, -25) -> (14.8, -25)
  line L20 (14.8, -25) -> (18.5, -25)
  line L21 (18.5, -25) -> (18.5, -27)
ref_plane "WorkPlane128" through (90.4, 0, 0) normal (1, 0, 0) x (0, 1, 0)
sketch "cheekL_pb09" plane through (90.4, 0, 0) normal (1, 0, 0) x (0, 0, -1)
  line L0 (18.5, -27) -> (14.8, -27)
  line L1 (14.8, -27) -> (11.1, -27)
  line L2 (11.1, -27) -> (7.4, -27)
  line L3 (7.4, -27) -> (3.7, -27)
  line L4 (3.7, -27) -> (0, -27)
  line L5 (0, -27) -> (-3.7, -27)
  line L6 (-3.7, -27) -> (-7.4, -27)
  line L7 (-7.4, -27) -> (-11.1, -27)
  line L8 (-11.1, -27) -> (-14.8, -27)
  line L9 (-14.8, -27) -> (-18.5, -27)
  line L10 (-18.5, -27) -> (-18.5, -25)
  line L11 (-18.5, -25) -> (-14.8, -25)
  line L12 (-14.8, -25) -> (-11.1, -25)
  line L13 (-11.1, -25) -> (-7.4, -25)
  line L14 (-7.4, -25) -> (-3.7, -25)
  line L15 (-3.7, -25) -> (0, -25)
  line L16 (0, -25) -> (3.7, -25)
  line L17 (3.7, -25) -> (7.4, -25)
  line L18 (7.4, -25) -> (11.1, -25)
  line L19 (11.1, -25) -> (14.8, -25)
  line L20 (14.8, -25) -> (18.5, -25)
  line L21 (18.5, -25) -> (18.5, -27)
loft "Loft64" add profiles "cheekL_pa09", "cheekL_pb09" section 1 section 2 separate body makes body 64
ref_plane "WorkPlane129" through (89.6, 0, 0) normal (1, 0, 0) x (0, 1, 0)
sketch "cheekL_pa10" plane through (89.6, 0, 0) normal (1, 0, 0) x (0, 0, -1)
  line L0 (18.5, -27) -> (14.8, -27)
  line L1 (14.8, -27) -> (11.1, -27)
  line L2 (11.1, -27) -> (7.4, -27)
  line L3 (7.4, -27) -> (3.7, -27)
  line L4 (3.7, -27) -> (0, -27)
  line L5 (0, -27) -> (-3.7, -27)
  line L6 (-3.7, -27) -> (-7.4, -27)
  line L7 (-7.4, -27) -> (-11.1, -27)
  line L8 (-11.1, -27) -> (-14.8, -27)
  line L9 (-14.8, -27) -> (-18.5, -27)
  line L10 (-18.5, -27) -> (-18.5, -25)
  line L11 (-18.5, -25) -> (-14.8, -25)
  line L12 (-14.8, -25) -> (-11.1, -25)
  line L13 (-11.1, -25) -> (-7.4, -25)
  line L14 (-7.4, -25) -> (-3.7, -25)
  line L15 (-3.7, -25) -> (0, -25)
  line L16 (0, -25) -> (3.7, -25)
  line L17 (3.7, -25) -> (7.4, -25)
  line L18 (7.4, -25) -> (11.1, -25)
  line L19 (11.1, -25) -> (14.8, -25)
  line L20 (14.8, -25) -> (18.5, -25)
  line L21 (18.5, -25) -> (18.5, -27)
ref_plane "WorkPlane130" through (120.4, 0, 0) normal (1, 0, 0) x (0, 1, 0)
sketch "cheekL_pb10" plane through (120.4, 0, 0) normal (1, 0, 0) x (0, 0, -1)
  line L0 (18.5, -27) -> (14.8, -27)
  line L1 (14.8, -27) -> (11.1, -27)
  line L2 (11.1, -27) -> (7.4, -27)
  line L3 (7.4, -27) -> (3.7, -27)
  line L4 (3.7, -27) -> (0, -27)
  line L5 (0, -27) -> (-3.7, -27)
  line L6 (-3.7, -27) -> (-7.4, -27)
  line L7 (-7.4, -27) -> (-11.1, -27)
  line L8 (-11.1, -27) -> (-14.8, -27)
  line L9 (-14.8, -27) -> (-18.5, -27)
  line L10 (-18.5, -27) -> (-18.5, -25)
  line L11 (-18.5, -25) -> (-14.8, -25)
  line L12 (-14.8, -25) -> (-11.1, -25)
  line L13 (-11.1, -25) -> (-7.4, -25)
  line L14 (-7.4, -25) -> (-3.7, -25)
  line L15 (-3.7, -25) -> (0, -25)
  line L16 (0, -25) -> (3.7, -25)
  line L17 (3.7, -25) -> (7.4, -25)
  line L18 (7.4, -25) -> (11.1, -25)
  line L19 (11.1, -25) -> (14.8, -25)
  line L20 (14.8, -25) -> (18.5, -25)
  line L21 (18.5, -25) -> (18.5, -27)
loft "Loft65" add profiles "cheekL_pa10", "cheekL_pb10" section 1 section 2 separate body makes body 65
ref_plane "WorkPlane131" through (119.6, 0, 0) normal (1, 0, 0) x (0, 1, 0)
sketch "cheekL_pa11" plane through (119.6, 0, 0) normal (1, 0, 0) x (0, 0, -1)
  line L0 (18.5, -27) -> (14.8, -27)
  line L1 (14.8, -27) -> (11.1, -27)
  line L2 (11.1, -27) -> (7.4, -27)
  line L3 (7.4, -27) -> (3.7, -27)
  line L4 (3.7, -27) -> (0, -27)
  line L5 (0, -27) -> (-3.7, -27)
  line L6 (-3.7, -27) -> (-7.4, -27)
  line L7 (-7.4, -27) -> (-11.1, -27)
  line L8 (-11.1, -27) -> (-14.8, -27)
  line L9 (-14.8, -27) -> (-18.5, -27)
  line L10 (-18.5, -27) -> (-18.5, -25)
  line L11 (-18.5, -25) -> (-14.8, -25)
  line L12 (-14.8, -25) -> (-11.1, -25)
  line L13 (-11.1, -25) -> (-7.4, -25)
  line L14 (-7.4, -25) -> (-3.7, -25)
  line L15 (-3.7, -25) -> (0, -25)
  line L16 (0, -25) -> (3.7, -25)
  line L17 (3.7, -25) -> (7.4, -25)
  line L18 (7.4, -25) -> (11.1, -25)
  line L19 (11.1, -25) -> (14.8, -25)
  line L20 (14.8, -25) -> (18.5, -25)
  line L21 (18.5, -25) -> (18.5, -27)
ref_plane "WorkPlane132" through (124.6857, 0, 0) normal (1, 0, 0) x (0, 1, 0)
sketch "cheekL_pb11" plane through (124.6857, 0, 0) normal (1, 0, 0) x (0, 0, -1)
  line L0 (16.3003, -24.3221) -> (13.0402, -24.3221)
  line L1 (13.0402, -24.3221) -> (9.7802, -24.3221)
  line L2 (9.7802, -24.3221) -> (6.5201, -24.3221)
  line L3 (6.5201, -24.3221) -> (3.2601, -24.3221)
  line L4 (3.2601, -24.3221) -> (0, -24.3221)
  line L5 (0, -24.3221) -> (-3.2601, -24.3221)
  line L6 (-3.2601, -24.3221) -> (-6.5201, -24.3221)
  line L7 (-6.5201, -24.3221) -> (-9.7802, -24.3221)
  line L8 (-9.7802, -24.3221) -> (-13.0402, -24.3221)
  line L9 (-13.0402, -24.3221) -> (-16.3003, -24.3221)
  line L10 (-16.3003, -24.3221) -> (-16.3003, -22.3221)
  line L11 (-16.3003, -22.3221) -> (-13.0402, -22.3221)
  line L12 (-13.0402, -22.3221) -> (-9.7802, -22.3221)
  line L13 (-9.7802, -22.3221) -> (-6.5201, -22.3221)
  line L14 (-6.5201, -22.3221) -> (-3.2601, -22.3221)
  line L15 (-3.2601, -22.3221) -> (0, -22.3221)
  line L16 (0, -22.3221) -> (3.2601, -22.3221)
  line L17 (3.2601, -22.3221) -> (6.5201, -22.3221)
  line L18 (6.5201, -22.3221) -> (9.7802, -22.3221)
  line L19 (9.7802, -22.3221) -> (13.0402, -22.3221)
  line L20 (13.0402, -22.3221) -> (16.3003, -22.3221)
  line L21 (16.3003, -22.3221) -> (16.3003, -24.3221)
loft "Loft66" add profiles "cheekL_pa11", "cheekL_pb11" section 1 section 2 separate body makes body 66
ref_plane "WorkPlane133" through (123.8857, 0, 0) normal (1, 0, 0) x (0, 1, 0)
sketch "cheekL_pa12" plane through (123.8857, 0, 0) normal (1, 0, 0) x (0, 0, -1)
  line L0 (16.3003, -24.3221) -> (13.0402, -24.3221)
  line L1 (13.0402, -24.3221) -> (9.7802, -24.3221)
  line L2 (9.7802, -24.3221) -> (6.5201, -24.3221)
  line L3 (6.5201, -24.3221) -> (3.2601, -24.3221)
  line L4 (3.2601, -24.3221) -> (0, -24.3221)
  line L5 (0, -24.3221) -> (-3.2601, -24.3221)
  line L6 (-3.2601, -24.3221) -> (-6.5201, -24.3221)
  line L7 (-6.5201, -24.3221) -> (-9.7802, -24.3221)
  line L8 (-9.7802, -24.3221) -> (-13.0402, -24.3221)
  line L9 (-13.0402, -24.3221) -> (-16.3003, -24.3221)
  line L10 (-16.3003, -24.3221) -> (-16.3003, -22.3221)
  line L11 (-16.3003, -22.3221) -> (-13.0402, -22.3221)
  line L12 (-13.0402, -22.3221) -> (-9.7802, -22.3221)
  line L13 (-9.7802, -22.3221) -> (-6.5201, -22.3221)
  line L14 (-6.5201, -22.3221) -> (-3.2601, -22.3221)
  line L15 (-3.2601, -22.3221) -> (0, -22.3221)
  line L16 (0, -22.3221) -> (3.2601, -22.3221)
  line L17 (3.2601, -22.3221) -> (6.5201, -22.3221)
  line L18 (6.5201, -22.3221) -> (9.7802, -22.3221)
  line L19 (9.7802, -22.3221) -> (13.0402, -22.3221)
  line L20 (13.0402, -22.3221) -> (16.3003, -22.3221)
  line L21 (16.3003, -22.3221) -> (16.3003, -24.3221)
ref_plane "WorkPlane134" through (128.9714, 0, 0) normal (1, 0, 0) x (0, 1, 0)